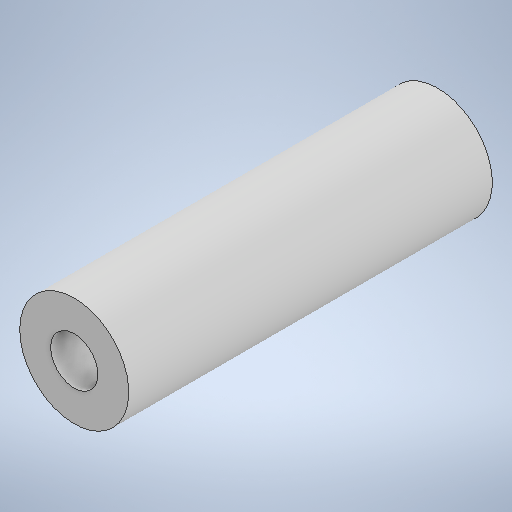
# Autodesk Inventor part: plateau_grand_robot_distance
Saved by Autodesk Inventor 2025.3 (Build 293356000, 356)
## iProperties
Created: 2025-05-12
Part Number: plateau_grand_robot_distance
Material: Generisch
Document SubType Name: Modeling
Designer: karle
Density: 1 g/cm^3
Appearance: Vorgabe
Author: karle
Autodesk Inventor part; units mm, degrees
ref_plane "YZ Plane" through (0, 0, 0) normal (1, 0, 0) x (0, 1, 0)
ref_plane "XZ Plane" through (0, 0, 0) normal (0, 1, 0) x (-1, 0, 0)
ref_plane "XY Plane" through (0, 0, 0) normal (0, 0, 1) x (1, 0, 0)
sketch "Skizze1" plane through (0, 0, 0) normal (0, 0, 1) x (1, 0, 0)
  line L0 (0, 91.9481) -> (0, -76.6234)
  line L1 (0, -19.8701) -> (-7.5, -19.8701)
  line L2 (-7.5, -19.8701) -> (-7.5, -69.8701)
  line L3 (-7.5, -69.8701) -> (0, -69.8701)
  line L4 (0, -19.8701) -> (0, -69.8701)
  point P0 (0, 0)
  point P1 (-3.75, -69.8701)
  point P2 (-3.75, -19.8701)
  dimension "d0" = 15
  dimension "d1" = 50
  dimension "d10" = 0
  constraints: 10 end point, 2 midpoint, 2 perpendicular, 2 point on line, 2 vertical, 1 horizontal
  measures "d0" diameter of L2 L0
  measures "d1" distance of point (-3.75, -69.87) point (-3.75, -19.87)
  measures "d10" distance from line of point (0, 0) L0
revolve "Umdrehung1" add sketch "Skizze1" angle 360 about axis through (0, 91.9481, 0) along (0, -1, 0)
sketch "Skizze2" plane through (0, -19.8701, 0) normal (0, 1, 0) x (1, 0, 0)
  point P0 (0, 0)
  point P1 (0, 0)
  constraints: 1 coincident
hole "Bohrung1" at (0, -19.8701, 0) direction (0, -1, 0) diameter 6.5 end through all
